210202_P01_WALL-PANEL-ASSY-BACK-LOWER-B2_CAD (Autodesk Fusion 360 design; units mm, degrees)
description: WALL - PANEL ASSY - BACK LOWER - B2 | Vách hậu - cụm tấm dưới phải | P01 | position B2
part number: 210202
description: WALL - PANEL FRAME - BACK LOWER - B2 | Vách hậu - khung dưới phải | P01
part number: 211202
description: WALL - SKIN - BACK LOWER - B2 | Vách hậu - tấm ốp alu dưới phải | P01
part number: 211402
description: WALL - CAVITY FILL - BACK LOWER - B2 | Vách hậu - bông PET dưới phải | P01
part number: 211602
description: HARDWARE - STOP WASHER - Ø10.5 X Ø20 X 1.5 - AL | Long đen chặn nhôm | P01
part number: 831002
description: HARDWARE - RIVET NUT - M6 - SHEREX CAH3-610-4.2 | Tán rút M6 | P01
part number: 838003
description: HARDWARE - LOCATING SPIGOT - M6 X Ø8 - STAINLESS | Chốt định vị Ø8 | P01
part number: 831001
Autodesk Fusion 360 part; units mm, degrees
(part 1 of 2)
ref_plane "WorkPlane1" through (0, 0, 112.26) normal (0, 0, 1) x (1, 0, 0) in component "211202 WALL - PANEL FRAME - BACK LOWER - B2"
sketch "SKETCH - RAIL - BOTTOM TUBE" plane through (0, 0, 112.26) normal (0, 0, 1) x (1, 0, 0) in component "211202 WALL - PANEL FRAME - BACK LOWER - B2"
  line L0 (2.75, 804) -> (1201.74, 804)
  line L1 (1201.74, 804) -> (1201.74, 844)
  line L2 (1201.74, 844) -> (2.75, 844)
  line L3 (2.75, 844) -> (2.75, 804)
  dimension "d175" = 1198.99
  dimension "d176" = 40
  dimension "d177" = 2.75
  dimension "d178" = 804
  constraint horizontal L0
  constraint vertical L1
  constraint horizontal L2
  constraint vertical L3
  measures "d175" horizontal distance of L0.start L0.end
  measures "d176" vertical distance of L0.start L2.end
  measures "d177" horizontal distance of origin L0.start
  measures "d178" vertical distance of origin L0.start
extrude "EXTRUDE - RAIL - BOTTOM TUBE" add sketch "SKETCH - RAIL - BOTTOM TUBE" along normal blind 20 makes body 1 in component "211202 WALL - PANEL FRAME - BACK LOWER - B2"
ref_plane "WorkPlane2" through (0, 0, 113.46) normal (0, 0, 1) x (1, 0, 0) in component "211202 WALL - PANEL FRAME - BACK LOWER - B2"
sketch "SKETCH - RAIL - BOTTOM BORE" plane through (0, 0, 113.46) normal (0, 0, 1) x (1, 0, 0) in component "211202 WALL - PANEL FRAME - BACK LOWER - B2"
  line L0 (2.75, 805.2) -> (1201.74, 805.2)
  line L1 (1201.74, 805.2) -> (1201.74, 842.8)
  line L2 (1201.74, 842.8) -> (2.75, 842.8)
  line L3 (2.75, 842.8) -> (2.75, 805.2)
  dimension "d183" = 1198.99
  dimension "d184" = 37.6
  dimension "d185" = 2.75
  dimension "d186" = 805.2
  constraint horizontal L0
  constraint vertical L1
  constraint horizontal L2
  constraint vertical L3
  measures "d183" horizontal distance of L0.start L0.end
  measures "d184" vertical distance of L0.start L2.end
  measures "d185" horizontal distance of origin L0.start
  measures "d186" vertical distance of origin L0.start
extrude "CUT - RAIL - BOTTOM BORE" cut sketch "SKETCH - RAIL - BOTTOM BORE" along normal blind 17.6 bodies 1 in component "211202 WALL - PANEL FRAME - BACK LOWER - B2"
ref_plane "WorkPlane3" through (0, 0, 1210.87) normal (0, 0, 1) x (1, 0, 0) in component "211202 WALL - PANEL FRAME - BACK LOWER - B2"
sketch "SKETCH - RAIL - TOP TUBE" plane through (0, 0, 1210.87) normal (0, 0, 1) x (1, 0, 0) in component "211202 WALL - PANEL FRAME - BACK LOWER - B2"
  line L0 (2.75, 804) -> (1201.74, 804)
  line L1 (1201.74, 804) -> (1201.74, 844)
  line L2 (1201.74, 844) -> (2.75, 844)
  line L3 (2.75, 844) -> (2.75, 804)
  dimension "d191" = 1198.99
  dimension "d192" = 40
  dimension "d193" = 2.75
  dimension "d194" = 804
  constraint horizontal L0
  constraint vertical L1
  constraint horizontal L2
  constraint vertical L3
  measures "d191" horizontal distance of L0.start L0.end
  measures "d192" vertical distance of L0.start L2.end
  measures "d193" horizontal distance of origin L0.start
  measures "d194" vertical distance of origin L0.start
extrude "EXTRUDE - RAIL - TOP TUBE" add sketch "SKETCH - RAIL - TOP TUBE" along normal blind 20 separate body makes body 2 in component "211202 WALL - PANEL FRAME - BACK LOWER - B2"
ref_plane "WorkPlane4" through (0, 0, 1212.07) normal (0, 0, 1) x (1, 0, 0) in component "211202 WALL - PANEL FRAME - BACK LOWER - B2"
sketch "SKETCH - RAIL - TOP BORE" plane through (0, 0, 1212.07) normal (0, 0, 1) x (1, 0, 0) in component "211202 WALL - PANEL FRAME - BACK LOWER - B2"
  line L0 (2.75, 805.2) -> (1201.74, 805.2)
  line L1 (1201.74, 805.2) -> (1201.74, 842.8)
  line L2 (1201.74, 842.8) -> (2.75, 842.8)
  line L3 (2.75, 842.8) -> (2.75, 805.2)
  dimension "d199" = 1198.99
  dimension "d200" = 37.6
  dimension "d201" = 2.75
  dimension "d202" = 805.2
  constraint horizontal L0
  constraint vertical L1
  constraint horizontal L2
  constraint vertical L3
  measures "d199" horizontal distance of L0.start L0.end
  measures "d200" vertical distance of L0.start L2.end
  measures "d201" horizontal distance of origin L0.start
  measures "d202" vertical distance of origin L0.start
extrude "CUT - RAIL - TOP BORE" cut sketch "SKETCH - RAIL - TOP BORE" along normal blind 17.6 bodies 2 in component "211202 WALL - PANEL FRAME - BACK LOWER - B2"
ref_plane "WorkPlane5" through (0, 0, 132.26) normal (0, 0, 1) x (1, 0, 0) in component "211202 WALL - PANEL FRAME - BACK LOWER - B2"
sketch "SKETCH - STILE - CENTRE TUBE" plane through (0, 0, 132.26) normal (0, 0, 1) x (1, 0, 0) in component "211202 WALL - PANEL FRAME - BACK LOWER - B2"
  line L0 (2.75, 804) -> (22.75, 804)
  line L1 (22.75, 804) -> (22.75, 844)
  line L2 (22.75, 844) -> (2.75, 844)
  line L3 (2.75, 844) -> (2.75, 804)
  dimension "d207" = 20
  dimension "d208" = 40
  dimension "d209" = 2.75
  dimension "d210" = 804
  constraint horizontal L0
  constraint vertical L1
  constraint horizontal L2
  constraint vertical L3
  measures "d207" horizontal distance of L0.start L0.end
  measures "d208" vertical distance of L0.start L2.end
  measures "d209" horizontal distance of origin L0.start
  measures "d210" vertical distance of origin L0.start
extrude "EXTRUDE - STILE - CENTRE TUBE" add sketch "SKETCH - STILE - CENTRE TUBE" along normal blind 1078.61 separate body makes body 3 in component "211202 WALL - PANEL FRAME - BACK LOWER - B2"
ref_plane "WorkPlane6" through (0, 0, 132.26) normal (0, 0, 1) x (1, 0, 0) in component "211202 WALL - PANEL FRAME - BACK LOWER - B2"
sketch "SKETCH - STILE - CENTRE BORE" plane through (0, 0, 132.26) normal (0, 0, 1) x (1, 0, 0) in component "211202 WALL - PANEL FRAME - BACK LOWER - B2"
  line L0 (3.95, 805.2) -> (21.55, 805.2)
  line L1 (21.55, 805.2) -> (21.55, 842.8)
  line L2 (21.55, 842.8) -> (3.95, 842.8)
  line L3 (3.95, 842.8) -> (3.95, 805.2)
  dimension "d215" = 17.6
  dimension "d216" = 37.6
  dimension "d217" = 3.95
  dimension "d218" = 805.2
  constraint horizontal L0
  constraint vertical L1
  constraint horizontal L2
  constraint vertical L3
  measures "d215" horizontal distance of L0.start L0.end
  measures "d216" vertical distance of L0.start L2.end
  measures "d217" horizontal distance of origin L0.start
  measures "d218" vertical distance of origin L0.start
extrude "CUT - STILE - CENTRE BORE" cut sketch "SKETCH - STILE - CENTRE BORE" along normal blind 1078.61 bodies 3 in component "211202 WALL - PANEL FRAME - BACK LOWER - B2"
ref_plane "WorkPlane7" through (0, 0, 132.26) normal (0, 0, 1) x (1, 0, 0) in component "211202 WALL - PANEL FRAME - BACK LOWER - B2"
sketch "SKETCH - STILE - OUTER TUBE" plane through (0, 0, 132.26) normal (0, 0, 1) x (1, 0, 0) in component "211202 WALL - PANEL FRAME - BACK LOWER - B2"
  line L0 (1181.74, 804) -> (1201.74, 804)
  line L1 (1201.74, 804) -> (1201.74, 844)
  line L2 (1201.74, 844) -> (1181.74, 844)
  line L3 (1181.74, 844) -> (1181.74, 804)
  dimension "d223" = 20
  dimension "d224" = 40
  dimension "d225" = 1181.74
  dimension "d226" = 804
  constraint horizontal L0
  constraint vertical L1
  constraint horizontal L2
  constraint vertical L3
  measures "d223" horizontal distance of L0.start L0.end
  measures "d224" vertical distance of L0.start L2.end
  measures "d225" horizontal distance of origin L0.start
  measures "d226" vertical distance of origin L0.start
extrude "EXTRUDE - STILE - OUTER TUBE" add sketch "SKETCH - STILE - OUTER TUBE" along normal blind 1078.61 separate body makes body 4 in component "211202 WALL - PANEL FRAME - BACK LOWER - B2"
ref_plane "WorkPlane8" through (0, 0, 132.26) normal (0, 0, 1) x (1, 0, 0) in component "211202 WALL - PANEL FRAME - BACK LOWER - B2"
sketch "SKETCH - STILE - OUTER BORE" plane through (0, 0, 132.26) normal (0, 0, 1) x (1, 0, 0) in component "211202 WALL - PANEL FRAME - BACK LOWER - B2"
  line L0 (1182.94, 805.2) -> (1200.54, 805.2)
  line L1 (1200.54, 805.2) -> (1200.54, 842.8)
  line L2 (1200.54, 842.8) -> (1182.94, 842.8)
  line L3 (1182.94, 842.8) -> (1182.94, 805.2)
  dimension "d231" = 17.6
  dimension "d232" = 37.6
  dimension "d233" = 1182.94
  dimension "d234" = 805.2
  constraint horizontal L0
  constraint vertical L1
  constraint horizontal L2
  constraint vertical L3
  measures "d231" horizontal distance of L0.start L0.end
  measures "d232" vertical distance of L0.start L2.end
  measures "d233" horizontal distance of origin L0.start
  measures "d234" vertical distance of origin L0.start
extrude "CUT - STILE - OUTER BORE" cut sketch "SKETCH - STILE - OUTER BORE" along normal blind 1078.61 bodies 4 in component "211202 WALL - PANEL FRAME - BACK LOWER - B2"
ref_plane "WorkPlane9" through (0, 0, 132.26) normal (0, 0, 1) x (1, 0, 0) in component "211202 WALL - PANEL FRAME - BACK LOWER - B2"
sketch "SKETCH - STILE - MID 1 TUBE" plane through (0, 0, 132.26) normal (0, 0, 1) x (1, 0, 0) in component "211202 WALL - PANEL FRAME - BACK LOWER - B2"
  line L0 (395.7467, 804) -> (415.7467, 804)
  line L1 (415.7467, 804) -> (415.7467, 844)
  line L2 (415.7467, 844) -> (395.7467, 844)
  line L3 (395.7467, 844) -> (395.7467, 804)
  dimension "d239" = 20
  dimension "d240" = 40
  dimension "d241" = 395.7467
  dimension "d242" = 804
  constraint horizontal L0
  constraint vertical L1
  constraint horizontal L2
  constraint vertical L3
  measures "d239" horizontal distance of L0.start L0.end
  measures "d240" vertical distance of L0.start L2.end
  measures "d241" horizontal distance of origin L0.start
  measures "d242" vertical distance of origin L0.start
extrude "EXTRUDE - STILE - MID 1 TUBE" add sketch "SKETCH - STILE - MID 1 TUBE" along normal blind 1078.61 separate body makes body 5 in component "211202 WALL - PANEL FRAME - BACK LOWER - B2"
ref_plane "WorkPlane10" through (0, 0, 132.26) normal (0, 0, 1) x (1, 0, 0) in component "211202 WALL - PANEL FRAME - BACK LOWER - B2"
sketch "SKETCH - STILE - MID 1 BORE" plane through (0, 0, 132.26) normal (0, 0, 1) x (1, 0, 0) in component "211202 WALL - PANEL FRAME - BACK LOWER - B2"
  line L0 (396.7467, 805) -> (414.7467, 805)
  line L1 (414.7467, 805) -> (414.7467, 843)
  line L2 (414.7467, 843) -> (396.7467, 843)
  line L3 (396.7467, 843) -> (396.7467, 805)
  dimension "d247" = 18
  dimension "d248" = 38
  dimension "d249" = 396.7467
  dimension "d250" = 805
  constraint horizontal L0
  constraint vertical L1
  constraint horizontal L2
  constraint vertical L3
  measures "d247" horizontal distance of L0.start L0.end
  measures "d248" vertical distance of L0.start L2.end
  measures "d249" horizontal distance of origin L0.start
  measures "d250" vertical distance of origin L0.start
extrude "CUT - STILE - MID 1 BORE" cut sketch "SKETCH - STILE - MID 1 BORE" along normal blind 1078.61 bodies 5 in component "211202 WALL - PANEL FRAME - BACK LOWER - B2"
pattern_linear "PATTERN - STILES - MID" count 2 spacing 392.9967 along (1, 0, 0) of bodies 5 makes body 6 in component "211202 WALL - PANEL FRAME - BACK LOWER - B2"
ref_plane "WorkPlane1" through (0, 0, 112.26) normal (0, 0, 1) x (1, 0, 0) in component "211402 WALL - SKIN - BACK LOWER - B2"
sketch "SKETCH - SKIN PLATE" plane through (0, 0, 112.26) normal (0, 0, 1) x (1, 0, 0) in component "211402 WALL - SKIN - BACK LOWER - B2"
  line L0 (1.13, 847) -> (1201.74, 847)
  line L1 (1201.74, 847) -> (1201.74, 850)
  line L2 (1201.74, 850) -> (1.13, 850)
  line L3 (1.13, 850) -> (1.13, 847)
  dimension "d259" = 1200.61
  dimension "d260" = 3
  dimension "d261" = 1.13
  dimension "d262" = 847
  constraint horizontal L0
  constraint vertical L1
  constraint horizontal L2
  constraint vertical L3
  measures "d259" horizontal distance of L0.start L0.end
  measures "d260" vertical distance of L0.start L2.end
  measures "d261" horizontal distance of origin L0.start
  measures "d262" vertical distance of origin L0.start
extrude "EXTRUDE - SKIN PLATE" add sketch "SKETCH - SKIN PLATE" along normal blind 1118.61 separate body makes body 7 in component "211402 WALL - SKIN - BACK LOWER - B2"
ref_plane "WorkPlane2" through (0, 850, 0) normal (0, 1, 0) x (0, 0, 1) in component "211402 WALL - SKIN - BACK LOWER - B2"
sketch "HOLE CENTRE - SKIN MAINS INLET" plane through (0, 850, 0) normal (0, 1, 0) x (1, 0, 0) in component "211402 WALL - SKIN - BACK LOWER - B2"
  point P0 (120, -313)
  dimension "d267" = 120
  dimension "d268" = 313
  measures "d267" horizontal distance of origin P0
  measures "d268" vertical distance of origin P0
hole "HOLE - SKIN MAINS INLET" at (120, 850, 313) direction (0, -1, 0) diameter 24 depth 4 tip angle 118 bodies 7 in component "211402 WALL - SKIN - BACK LOWER - B2"
ref_plane "WorkPlane3" through (0, 850, 0) normal (0, 1, 0) x (0, 0, 1) in component "211402 WALL - SKIN - BACK LOWER - B2"
sketch "HOLE CENTRE - SKIN LAN FEED-THROUGH" plane through (0, 850, 0) normal (0, 1, 0) x (1, 0, 0) in component "211402 WALL - SKIN - BACK LOWER - B2"
  point P0 (120, -375)
  dimension "d274" = 120
  dimension "d275" = 375
  measures "d274" horizontal distance of origin P0
  measures "d275" vertical distance of origin P0
hole "HOLE - SKIN LAN FEED-THROUGH" at (120, 850, 375) direction (0, -1, 0) diameter 24 depth 4 tip angle 118 bodies 7 in component "211402 WALL - SKIN - BACK LOWER - B2"
ref_plane "WorkPlane1" through (0, 0, 132.26) normal (0, 0, 1) x (1, 0, 0) in component "211602 WALL - CAVITY FILL - BACK LOWER - B2"
sketch "SKETCH - FILL BAY 1" plane through (0, 0, 132.26) normal (0, 0, 1) x (1, 0, 0) in component "211602 WALL - CAVITY FILL - BACK LOWER - B2"
  line L0 (22.75, 804) -> (395.7467, 804)
  line L1 (395.7467, 804) -> (395.7467, 844)
  line L2 (395.7467, 844) -> (22.75, 844)
  line L3 (22.75, 844) -> (22.75, 804)
  dimension "d281" = 372.9967
  dimension "d282" = 40
  dimension "d283" = 22.75
  dimension "d284" = 804
  constraint horizontal L0
  constraint vertical L1
  constraint horizontal L2
  constraint vertical L3
  measures "d281" horizontal distance of L0.start L0.end
  measures "d282" vertical distance of L0.start L2.end
  measures "d283" horizontal distance of origin L0.start
  measures "d284" vertical distance of origin L0.start
extrude "EXTRUDE - FILL BAY 1" add sketch "SKETCH - FILL BAY 1" along normal blind 1078.61 separate body makes body 8 in component "211602 WALL - CAVITY FILL - BACK LOWER - B2"
pattern_linear "PATTERN - FILL BAYS" count 3 spacing 392.9967 along (1, 0, 0) of bodies 8 makes body 9 at (664.4111, 844, 851.3333) makes body 10 at (1057.4078, 844, 851.3333) in component "211602 WALL - CAVITY FILL - BACK LOWER - B2"
ref_plane "WorkPlane2" through (0, 0, 132.26) normal (0, 0, 1) x (1, 0, 0) in component "211602 WALL - CAVITY FILL - BACK LOWER - B2"
sketch "SKETCH - FILL POCKET BOTTOM BOLT 1" plane through (0, 0, 132.26) normal (0, 0, 1) x (1, 0, 0) in component "211602 WALL - CAVITY FILL - BACK LOWER - B2"
  line L0 (192.75, 804) -> (252.75, 804)
  line L1 (252.75, 804) -> (252.75, 844)
  line L2 (252.75, 844) -> (192.75, 844)
  line L3 (192.75, 844) -> (192.75, 804)
  dimension "d293" = 60
  dimension "d294" = 40
  dimension "d295" = 192.75
  dimension "d296" = 804
  constraint horizontal L0
  constraint vertical L1
  constraint horizontal L2
  constraint vertical L3
  measures "d293" horizontal distance of L0.start L0.end
  measures "d294" vertical distance of L0.start L2.end
  measures "d295" horizontal distance of origin L0.start
  measures "d296" vertical distance of origin L0.start
extrude "CUT - FILL POCKET BOTTOM BOLT 1" cut sketch "SKETCH - FILL POCKET BOTTOM BOLT 1" along normal blind 60 bodies 8 in component "211602 WALL - CAVITY FILL - BACK LOWER - B2"
ref_plane "WorkPlane3" through (0, 0, 132.26) normal (0, 0, 1) x (1, 0, 0) in component "211602 WALL - CAVITY FILL - BACK LOWER - B2"
sketch "SKETCH - FILL POCKET BOTTOM BOLT 2" plane through (0, 0, 132.26) normal (0, 0, 1) x (1, 0, 0) in component "211602 WALL - CAVITY FILL - BACK LOWER - B2"
  line L0 (445.7467, 804) -> (505.7467, 804)
  line L1 (505.7467, 804) -> (505.7467, 844)
  line L2 (505.7467, 844) -> (445.7467, 844)
  line L3 (445.7467, 844) -> (445.7467, 804)
  dimension "d301" = 60
  dimension "d302" = 40
  dimension "d303" = 445.7467
  dimension "d304" = 804
  constraint horizontal L0
  constraint vertical L1
  constraint horizontal L2
  constraint vertical L3
  measures "d301" horizontal distance of L0.start L0.end
  measures "d302" vertical distance of L0.start L2.end
  measures "d303" horizontal distance of origin L0.start
  measures "d304" vertical distance of origin L0.start
extrude "CUT - FILL POCKET BOTTOM BOLT 2" cut sketch "SKETCH - FILL POCKET BOTTOM BOLT 2" along normal blind 60 bodies 9 in component "211602 WALL - CAVITY FILL - BACK LOWER - B2"
ref_plane "WorkPlane4" through (0, 0, 132.26) normal (0, 0, 1) x (1, 0, 0) in component "211602 WALL - CAVITY FILL - BACK LOWER - B2"
sketch "SKETCH - FILL POCKET BOTTOM BOLT 3" plane through (0, 0, 132.26) normal (0, 0, 1) x (1, 0, 0) in component "211602 WALL - CAVITY FILL - BACK LOWER - B2"
  line L0 (698.7433, 804) -> (758.7433, 804)
  line L1 (758.7433, 804) -> (758.7433, 844)
  line L2 (758.7433, 844) -> (698.7433, 844)
  line L3 (698.7433, 844) -> (698.7433, 804)
  dimension "d309" = 60
  dimension "d310" = 40
  dimension "d311" = 698.7433
  dimension "d312" = 804
  constraint horizontal L0
  constraint vertical L1
  constraint horizontal L2
  constraint vertical L3
  measures "d309" horizontal distance of L0.start L0.end
  measures "d310" vertical distance of L0.start L2.end
  measures "d311" horizontal distance of origin L0.start
  measures "d312" vertical distance of origin L0.start
extrude "CUT - FILL POCKET BOTTOM BOLT 3" cut sketch "SKETCH - FILL POCKET BOTTOM BOLT 3" along normal blind 60 bodies 9 in component "211602 WALL - CAVITY FILL - BACK LOWER - B2"
ref_plane "WorkPlane5" through (0, 0, 132.26) normal (0, 0, 1) x (1, 0, 0) in component "211602 WALL - CAVITY FILL - BACK LOWER - B2"
sketch "SKETCH - FILL POCKET BOTTOM BOLT 4" plane through (0, 0, 132.26) normal (0, 0, 1) x (1, 0, 0) in component "211602 WALL - CAVITY FILL - BACK LOWER - B2"
  line L0 (951.74, 804) -> (1011.74, 804)
  line L1 (1011.74, 804) -> (1011.74, 844)
  line L2 (1011.74, 844) -> (951.74, 844)
  line L3 (951.74, 844) -> (951.74, 804)
  dimension "d317" = 60
  dimension "d318" = 40
  dimension "d319" = 951.74
  dimension "d320" = 804
  constraint horizontal L0
  constraint vertical L1
  constraint horizontal L2
  constraint vertical L3
  measures "d317" horizontal distance of L0.start L0.end
  measures "d318" vertical distance of L0.start L2.end
  measures "d319" horizontal distance of origin L0.start
  measures "d320" vertical distance of origin L0.start
extrude "CUT - FILL POCKET BOTTOM BOLT 4" cut sketch "SKETCH - FILL POCKET BOTTOM BOLT 4" along normal blind 60 bodies 10 in component "211602 WALL - CAVITY FILL - BACK LOWER - B2"
ref_plane "WorkPlane6" through (0, 0, 302.26) normal (0, 0, 1) x (1, 0, 0) in component "211602 WALL - CAVITY FILL - BACK LOWER - B2"
sketch "SKETCH - FILL POCKET CORNER BOLT 1" plane through (0, 0, 302.26) normal (0, 0, 1) x (1, 0, 0) in component "211602 WALL - CAVITY FILL - BACK LOWER - B2"
  line L0 (1121.74, 804) -> (1181.74, 804)
  line L1 (1181.74, 804) -> (1181.74, 844)
  line L2 (1181.74, 844) -> (1121.74, 844)
  line L3 (1121.74, 844) -> (1121.74, 804)
  dimension "d325" = 60
  dimension "d326" = 40
  dimension "d327" = 1121.74
  dimension "d328" = 804
  constraint horizontal L0
  constraint vertical L1
  constraint horizontal L2
  constraint vertical L3
  measures "d325" horizontal distance of L0.start L0.end
  measures "d326" vertical distance of L0.start L2.end
  measures "d327" horizontal distance of origin L0.start
  measures "d328" vertical distance of origin L0.start
extrude "CUT - FILL POCKET CORNER BOLT 1" cut sketch "SKETCH - FILL POCKET CORNER BOLT 1" along normal blind 60 bodies 10 in component "211602 WALL - CAVITY FILL - BACK LOWER - B2"
ref_plane "WorkPlane7" through (0, 0, 641.565) normal (0, 0, 1) x (1, 0, 0) in component "211602 WALL - CAVITY FILL - BACK LOWER - B2"
sketch "SKETCH - FILL POCKET CORNER BOLT 2" plane through (0, 0, 641.565) normal (0, 0, 1) x (1, 0, 0) in component "211602 WALL - CAVITY FILL - BACK LOWER - B2"
  line L0 (1121.74, 804) -> (1181.74, 804)
  line L1 (1181.74, 804) -> (1181.74, 844)
  line L2 (1181.74, 844) -> (1121.74, 844)
  line L3 (1121.74, 844) -> (1121.74, 804)
  dimension "d333" = 60
  dimension "d334" = 40
  dimension "d335" = 1121.74
  dimension "d336" = 804
  constraint horizontal L0
  constraint vertical L1
  constraint horizontal L2
  constraint vertical L3
  measures "d333" horizontal distance of L0.start L0.end
  measures "d334" vertical distance of L0.start L2.end
  measures "d335" horizontal distance of origin L0.start
  measures "d336" vertical distance of origin L0.start
extrude "CUT - FILL POCKET CORNER BOLT 2" cut sketch "SKETCH - FILL POCKET CORNER BOLT 2" along normal blind 60 bodies 10 in component "211602 WALL - CAVITY FILL - BACK LOWER - B2"
ref_plane "WorkPlane8" through (0, 0, 980.87) normal (0, 0, 1) x (1, 0, 0) in component "211602 WALL - CAVITY FILL - BACK LOWER - B2"
sketch "SKETCH - FILL POCKET CORNER BOLT 3" plane through (0, 0, 980.87) normal (0, 0, 1) x (1, 0, 0) in component "211602 WALL - CAVITY FILL - BACK LOWER - B2"
  line L0 (1121.74, 804) -> (1181.74, 804)
  line L1 (1181.74, 804) -> (1181.74, 844)
  line L2 (1181.74, 844) -> (1121.74, 844)
  line L3 (1121.74, 844) -> (1121.74, 804)
  dimension "d341" = 60
  dimension "d342" = 40
  dimension "d343" = 1121.74
  dimension "d344" = 804
  constraint horizontal L0
  constraint vertical L1
  constraint horizontal L2
  constraint vertical L3
  measures "d341" horizontal distance of L0.start L0.end
  measures "d342" vertical distance of L0.start L2.end
  measures "d343" horizontal distance of origin L0.start
  measures "d344" vertical distance of origin L0.start
extrude "CUT - FILL POCKET CORNER BOLT 3" cut sketch "SKETCH - FILL POCKET CORNER BOLT 3" along normal blind 60 bodies 10 in component "211602 WALL - CAVITY FILL - BACK LOWER - B2"
ref_plane "WorkPlane9" through (0, 0, 302.26) normal (0, 0, 1) x (1, 0, 0) in component "211602 WALL - CAVITY FILL - BACK LOWER - B2"
sketch "SKETCH - FILL POCKET CLOSING SEAM BOLT 1" plane through (0, 0, 302.26) normal (0, 0, 1) x (1, 0, 0) in component "211602 WALL - CAVITY FILL - BACK LOWER - B2"
  line L0 (22.75, 804) -> (82.75, 804)
  line L1 (82.75, 804) -> (82.75, 844)
  line L2 (82.75, 844) -> (22.75, 844)
  line L3 (22.75, 844) -> (22.75, 804)
  dimension "d349" = 60
  dimension "d350" = 40
  dimension "d351" = 22.75
  dimension "d352" = 804
  constraint horizontal L0
  constraint vertical L1
  constraint horizontal L2
  constraint vertical L3
  measures "d349" horizontal distance of L0.start L0.end
  measures "d350" vertical distance of L0.start L2.end
  measures "d351" horizontal distance of origin L0.start
  measures "d352" vertical distance of origin L0.start
extrude "CUT - FILL POCKET CLOSING SEAM BOLT 1" cut sketch "SKETCH - FILL POCKET CLOSING SEAM BOLT 1" along normal blind 60 bodies 8 in component "211602 WALL - CAVITY FILL - BACK LOWER - B2"
ref_plane "WorkPlane10" through (0, 0, 641.565) normal (0, 0, 1) x (1, 0, 0) in component "211602 WALL - CAVITY FILL - BACK LOWER - B2"
sketch "SKETCH - FILL POCKET CLOSING SEAM BOLT 2" plane through (0, 0, 641.565) normal (0, 0, 1) x (1, 0, 0) in component "211602 WALL - CAVITY FILL - BACK LOWER - B2"
  line L0 (22.75, 804) -> (82.75, 804)
  line L1 (82.75, 804) -> (82.75, 844)
  line L2 (82.75, 844) -> (22.75, 844)
  line L3 (22.75, 844) -> (22.75, 804)
  dimension "d357" = 60
  dimension "d358" = 40
  dimension "d359" = 22.75
  dimension "d360" = 804
  constraint horizontal L0
  constraint vertical L1
  constraint horizontal L2
  constraint vertical L3
  measures "d357" horizontal distance of L0.start L0.end
  measures "d358" vertical distance of L0.start L2.end
  measures "d359" horizontal distance of origin L0.start
  measures "d360" vertical distance of origin L0.start
extrude "CUT - FILL POCKET CLOSING SEAM BOLT 2" cut sketch "SKETCH - FILL POCKET CLOSING SEAM BOLT 2" along normal blind 60 bodies 8 in component "211602 WALL - CAVITY FILL - BACK LOWER - B2"
ref_plane "WorkPlane11" through (0, 0, 980.87) normal (0, 0, 1) x (1, 0, 0) in component "211602 WALL - CAVITY FILL - BACK LOWER - B2"
sketch "SKETCH - FILL POCKET CLOSING SEAM BOLT 3" plane through (0, 0, 980.87) normal (0, 0, 1) x (1, 0, 0) in component "211602 WALL - CAVITY FILL - BACK LOWER - B2"
  line L0 (22.75, 804) -> (82.75, 804)
  line L1 (82.75, 804) -> (82.75, 844)
  line L2 (82.75, 844) -> (22.75, 844)
  line L3 (22.75, 844) -> (22.75, 804)
  dimension "d365" = 60
  dimension "d366" = 40
  dimension "d367" = 22.75
  dimension "d368" = 804
  constraint horizontal L0
  constraint vertical L1
  constraint horizontal L2
  constraint vertical L3
  measures "d365" horizontal distance of L0.start L0.end
  measures "d366" vertical distance of L0.start L2.end
  measures "d367" horizontal distance of origin L0.start
  measures "d368" vertical distance of origin L0.start
extrude "CUT - FILL POCKET CLOSING SEAM BOLT 3" cut sketch "SKETCH - FILL POCKET CLOSING SEAM BOLT 3" along normal blind 60 bodies 8 in component "211602 WALL - CAVITY FILL - BACK LOWER - B2"
ref_plane "WorkPlane12" through (0, 0, 866) normal (0, 0, 1) x (1, 0, 0) in component "211602 WALL - CAVITY FILL - BACK LOWER - B2"
sketch "SKETCH - FILL CUT-OUT POWER UNIT" plane through (0, 0, 866) normal (0, 0, 1) x (1, 0, 0) in component "211602 WALL - CAVITY FILL - BACK LOWER - B2"
  line L0 (91, 803) -> (405.7467, 803)
  line L1 (405.7467, 803) -> (405.7467, 845)
  line L2 (405.7467, 845) -> (91, 845)
  line L3 (91, 845) -> (91, 803)
  dimension "d373" = 314.7467
  dimension "d374" = 42
  dimension "d375" = 91
  dimension "d376" = 803
  constraint horizontal L0
  constraint vertical L1
  constraint horizontal L2
  constraint vertical L3
  measures "d373" horizontal distance of L0.start L0.end
  measures "d374" vertical distance of L0.start L2.end
  measures "d375" horizontal distance of origin L0.start
  measures "d376" vertical distance of origin L0.start
extrude "CUT - FILL CUT-OUT POWER UNIT" cut sketch "SKETCH - FILL CUT-OUT POWER UNIT" along normal blind 268 bodies 8 in component "211602 WALL - CAVITY FILL - BACK LOWER - B2"
ref_plane "WorkPlane13" through (0, 0, 301) normal (0, 0, 1) x (1, 0, 0) in component "211602 WALL - CAVITY FILL - BACK LOWER - B2"
sketch "SKETCH - FILL CUT-OUT SLEEVE" plane through (0, 0, 301) normal (0, 0, 1) x (1, 0, 0) in component "211602 WALL - CAVITY FILL - BACK LOWER - B2"
  line L0 (140, 803) -> (160, 803)
  line L1 (160, 803) -> (160, 845)
  line L2 (160, 845) -> (140, 845)
  line L3 (140, 845) -> (140, 803)
  dimension "d381" = 20
  dimension "d382" = 42
  dimension "d383" = 140
  dimension "d384" = 803
  constraint horizontal L0
  constraint vertical L1
  constraint horizontal L2
  constraint vertical L3
  measures "d381" horizontal distance of L0.start L0.end
  measures "d382" vertical distance of L0.start L2.end
  measures "d383" horizontal distance of origin L0.start
  measures "d384" vertical distance of origin L0.start
extrude "CUT - FILL CUT-OUT SLEEVE" cut sketch "SKETCH - FILL CUT-OUT SLEEVE" along normal blind 565 bodies 8 in component "211602 WALL - CAVITY FILL - BACK LOWER - B2"
ref_plane "WorkPlane14" through (0, 0, 301) normal (0, 0, 1) x (1, 0, 0) in component "211602 WALL - CAVITY FILL - BACK LOWER - B2"
sketch "SKETCH - FILL CUT-OUT INLET AND LAN" plane through (0, 0, 301) normal (0, 0, 1) x (1, 0, 0) in component "211602 WALL - CAVITY FILL - BACK LOWER - B2"
  line L0 (108, 803) -> (160, 803)
  line L1 (160, 803) -> (160, 845)
  line L2 (160, 845) -> (108, 845)
  line L3 (108, 845) -> (108, 803)
  dimension "d389" = 52
  dimension "d390" = 42
  dimension "d391" = 108
  dimension "d392" = 803
  constraint horizontal L0
  constraint vertical L1
  constraint horizontal L2
  constraint vertical L3
  measures "d389" horizontal distance of L0.start L0.end
  measures "d390" vertical distance of L0.start L2.end
  measures "d391" horizontal distance of origin L0.start
  measures "d392" vertical distance of origin L0.start
extrude "CUT - FILL CUT-OUT INLET AND LAN" cut sketch "SKETCH - FILL CUT-OUT INLET AND LAN" along normal blind 86 bodies 8 in component "211602 WALL - CAVITY FILL - BACK LOWER - B2"
ref_plane "WorkPlane11" through (0, 0, 112.26) normal (0, 0, 1) x (1, 0, 0) in component "211202 WALL - PANEL FRAME - BACK LOWER - B2"
sketch "HOLE CENTRE - BOTTOM RAIL BOLT CLEARANCE 1" plane through (0, 0, 112.26) normal (0, 0, 1) x (1, 0, 0) in component "211202 WALL - PANEL FRAME - BACK LOWER - B2"
  point P0 (222.75, 824)
  dimension "d397" = 222.75
  dimension "d398" = 824
  measures "d397" horizontal distance of origin P0
  measures "d398" vertical distance of origin P0
hole "HOLE - BOTTOM RAIL BOLT CLEARANCE 1" at (222.75, 824, 112.26) direction (0, 0, 1) diameter 7 depth 1.2 tip angle 118 bodies 1 in component "211202 WALL - PANEL FRAME - BACK LOWER - B2"
ref_plane "WorkPlane12" through (0, 0, 132.26) normal (0, 0, 1) x (1, 0, 0) in component "211202 WALL - PANEL FRAME - BACK LOWER - B2"
sketch "HOLE CENTRE - BOTTOM RAIL KEY ACCESS 1" plane through (0, 0, 132.26) normal (0, 0, 1) x (1, 0, 0) in component "211202 WALL - PANEL FRAME - BACK LOWER - B2"
  point P0 (222.75, 824)
  dimension "d404" = 222.75
  dimension "d405" = 824
  measures "d404" horizontal distance of origin P0
  measures "d405" vertical distance of origin P0
hole "HOLE - BOTTOM RAIL KEY ACCESS 1" at (222.75, 824, 132.26) direction (0, 0, -1) diameter 19 depth 1.2 tip angle 118 bodies 1 in component "211202 WALL - PANEL FRAME - BACK LOWER - B2"
pattern_linear "PATTERN - BOTTOM RAIL BOLT HOLES" count 4 spacing 252.9967 along (1, 0, 0) of "HOLE - BOTTOM RAIL BOLT CLEARANCE 1", "HOLE - BOTTOM RAIL KEY ACCESS 1" in component "211202 WALL - PANEL FRAME - BACK LOWER - B2"
ref_plane "WorkPlane13" through (0, 0, 112.26) normal (0, 0, 1) x (1, 0, 0) in component "211202 WALL - PANEL FRAME - BACK LOWER - B2"
sketch "HOLE CENTRE - BOTTOM RAIL SPIGOT ROUND" plane through (0, 0, 112.26) normal (0, 0, 1) x (1, 0, 0) in component "211202 WALL - PANEL FRAME - BACK LOWER - B2"
  point P0 (102.75, 824)
  dimension "d415" = 102.75
  dimension "d416" = 824
  measures "d415" horizontal distance of origin P0
  measures "d416" vertical distance of origin P0
hole "HOLE - BOTTOM RAIL SPIGOT ROUND" at (102.75, 824, 112.26) direction (0, 0, 1) diameter 8.5 depth 1.2 tip angle 118 bodies 1 in component "211202 WALL - PANEL FRAME - BACK LOWER - B2"
ref_plane "WorkPlane14" through (0, 0, 112.26) normal (0, 0, 1) x (1, 0, 0) in component "211202 WALL - PANEL FRAME - BACK LOWER - B2"
sketch "SKETCH - BOTTOM RAIL SPIGOT SLOT" plane through (0, 0, 112.26) normal (0, 0, 1) x (1, 0, 0) in component "211202 WALL - PANEL FRAME - BACK LOWER - B2"
  line L0 (1098.99, 819.75) -> (1104.49, 819.75)
  line L1 (1104.49, 819.75) -> (1104.49, 828.25)
  line L2 (1104.49, 828.25) -> (1098.99, 828.25)
  line L3 (1098.99, 828.25) -> (1098.99, 819.75)
  dimension "d422" = 5.5
  dimension "d423" = 8.5
  dimension "d424" = 1098.99
  dimension "d425" = 819.75
  constraint horizontal L0
  constraint vertical L1
  constraint horizontal L2
  constraint vertical L3
  measures "d422" horizontal distance of L0.start L0.end
  measures "d423" vertical distance of L0.start L2.end
  measures "d424" horizontal distance of origin L0.start
  measures "d425" vertical distance of origin L0.start
extrude "CUT - BOTTOM RAIL SPIGOT SLOT" cut sketch "SKETCH - BOTTOM RAIL SPIGOT SLOT" along normal blind 1.2 bodies 1 in component "211202 WALL - PANEL FRAME - BACK LOWER - B2"
ref_plane "WorkPlane15" through (0, 0, 112.26) normal (0, 0, 1) x (1, 0, 0) in component "211202 WALL - PANEL FRAME - BACK LOWER - B2"
sketch "HOLE CENTRE - BOTTOM RAIL SPIGOT SLOT END 1" plane through (0, 0, 112.26) normal (0, 0, 1) x (1, 0, 0) in component "211202 WALL - PANEL FRAME - BACK LOWER - B2"
  point P0 (1098.99, 824)
  dimension "d430" = 1098.99
  dimension "d431" = 824
  measures "d430" horizontal distance of origin P0
  measures "d431" vertical distance of origin P0
hole "HOLE - BOTTOM RAIL SPIGOT SLOT END 1" at (1098.99, 824, 112.26) direction (0, 0, 1) diameter 8.5 depth 1.2 tip angle 118 bodies 1 in component "211202 WALL - PANEL FRAME - BACK LOWER - B2"
ref_plane "WorkPlane16" through (0, 0, 112.26) normal (0, 0, 1) x (1, 0, 0) in component "211202 WALL - PANEL FRAME - BACK LOWER - B2"
sketch "HOLE CENTRE - BOTTOM RAIL SPIGOT SLOT END 2" plane through (0, 0, 112.26) normal (0, 0, 1) x (1, 0, 0) in component "211202 WALL - PANEL FRAME - BACK LOWER - B2"
  point P0 (1104.49, 824)
  dimension "d437" = 1104.49
  dimension "d438" = 824
  measures "d437" horizontal distance of origin P0
  measures "d438" vertical distance of origin P0
hole "HOLE - BOTTOM RAIL SPIGOT SLOT END 2" at (1104.49, 824, 112.26) direction (0, 0, 1) diameter 8.5 depth 1.2 tip angle 118 bodies 1 in component "211202 WALL - PANEL FRAME - BACK LOWER - B2"
ref_plane "WorkPlane17" through (0, 0, 1230.87) normal (0, 0, 1) x (1, 0, 0) in component "211202 WALL - PANEL FRAME - BACK LOWER - B2"
sketch "HOLE CENTRE - TOP RAIL RIVNUT 1" plane through (0, 0, 1230.87) normal (0, 0, 1) x (1, 0, 0) in component "211202 WALL - PANEL FRAME - BACK LOWER - B2"
  point P0 (222.75, 824)
  dimension "d444" = 222.75
  dimension "d445" = 824
  measures "d444" horizontal distance of origin P0
  measures "d445" vertical distance of origin P0
hole "HOLE - TOP RAIL RIVNUT 1" at (222.75, 824, 1230.87) direction (0, 0, -1) diameter 9.53 depth 1.2 tip angle 118 bodies 2 in component "211202 WALL - PANEL FRAME - BACK LOWER - B2"
pattern_linear "PATTERN - TOP RAIL RIVNUTS" count 4 spacing 252.9967 along (1, 0, 0) of "HOLE - TOP RAIL RIVNUT 1" in component "211202 WALL - PANEL FRAME - BACK LOWER - B2"
ref_plane "WorkPlane18" through (0, 0, 1230.87) normal (0, 0, 1) x (1, 0, 0) in component "211202 WALL - PANEL FRAME - BACK LOWER - B2"
sketch "HOLE CENTRE - TOP RAIL SPIGOT RIVNUT LOW X" plane through (0, 0, 1230.87) normal (0, 0, 1) x (1, 0, 0) in component "211202 WALL - PANEL FRAME - BACK LOWER - B2"
  point P0 (102.75, 824)
  dimension "d455" = 102.75
  dimension "d456" = 824
  measures "d455" horizontal distance of origin P0
  measures "d456" vertical distance of origin P0
hole "HOLE - TOP RAIL SPIGOT RIVNUT LOW X" at (102.75, 824, 1230.87) direction (0, 0, -1) diameter 9.53 depth 1.2 tip angle 118 bodies 2 in component "211202 WALL - PANEL FRAME - BACK LOWER - B2"
ref_plane "WorkPlane19" through (0, 0, 1230.87) normal (0, 0, 1) x (1, 0, 0) in component "211202 WALL - PANEL FRAME - BACK LOWER - B2"
sketch "HOLE CENTRE - TOP RAIL SPIGOT RIVNUT HIGH X" plane through (0, 0, 1230.87) normal (0, 0, 1) x (1, 0, 0) in component "211202 WALL - PANEL FRAME - BACK LOWER - B2"
  point P0 (1101.74, 824)
  dimension "d462" = 1101.74
  dimension "d463" = 824
  measures "d462" horizontal distance of origin P0
  measures "d463" vertical distance of origin P0
hole "HOLE - TOP RAIL SPIGOT RIVNUT HIGH X" at (1101.74, 824, 1230.87) direction (0, 0, -1) diameter 9.53 depth 1.2 tip angle 118 bodies 2 in component "211202 WALL - PANEL FRAME - BACK LOWER - B2"
ref_plane "WorkPlane20" through (1201.74, 0, 0) normal (1, 0, 0) x (0, 1, 0) in component "211202 WALL - PANEL FRAME - BACK LOWER - B2"
sketch "HOLE CENTRE - OUTER STILE CORNER BOLT CLEARANCE 1" plane through (1201.74, 0, 0) normal (1, 0, 0) x (0, 0, -1) in component "211202 WALL - PANEL FRAME - BACK LOWER - B2"
  point P0 (-332.26, 824)
  dimension "d469" = 824
  dimension "d470" = 332.26
  measures "d469" vertical distance of origin P0
  measures "d470" horizontal distance of origin P0
hole "HOLE - OUTER STILE CORNER BOLT CLEARANCE 1" at (1201.74, 824, 332.26) direction (-1, 0, 0) diameter 7 depth 1.2 tip angle 118 bodies 4 in component "211202 WALL - PANEL FRAME - BACK LOWER - B2"
ref_plane "WorkPlane21" through (1181.74, 0, 0) normal (1, 0, 0) x (0, 1, 0) in component "211202 WALL - PANEL FRAME - BACK LOWER - B2"
sketch "HOLE CENTRE - OUTER STILE CORNER KEY ACCESS 1" plane through (1181.74, 0, 0) normal (1, 0, 0) x (0, 0, -1) in component "211202 WALL - PANEL FRAME - BACK LOWER - B2"
  point P0 (-332.26, 824)
  dimension "d476" = 824
  dimension "d477" = 332.26
  measures "d476" vertical distance of origin P0
  measures "d477" horizontal distance of origin P0
hole "HOLE - OUTER STILE CORNER KEY ACCESS 1" at (1181.74, 824, 332.26) direction (1, 0, 0) diameter 19 depth 1.2 tip angle 118 bodies 4 in component "211202 WALL - PANEL FRAME - BACK LOWER - B2"
pattern_linear "PATTERN - OUTER STILE CORNER BOLT HOLES" count 3 spacing 339.305 along (0, 0, 1) of "HOLE - OUTER STILE CORNER BOLT CLEARANCE 1", "HOLE - OUTER STILE CORNER KEY ACCESS 1" in component "211202 WALL - PANEL FRAME - BACK LOWER - B2"
ref_plane "WorkPlane22" through (2.75, 0, 0) normal (1, 0, 0) x (0, 1, 0) in component "211202 WALL - PANEL FRAME - BACK LOWER - B2"
sketch "HOLE CENTRE - CENTRE STILE PIN RIVNUT 1" plane through (2.75, 0, 0) normal (1, 0, 0) x (0, 0, -1) in component "211202 WALL - PANEL FRAME - BACK LOWER - B2"
  point P0 (-332.26, 824)
  dimension "d487" = 824
  dimension "d488" = 332.26
  measures "d487" vertical distance of origin P0
  measures "d488" horizontal distance of origin P0
hole "HOLE - CENTRE STILE PIN RIVNUT 1" at (2.75, 824, 332.26) direction (1, 0, 0) diameter 9.53 depth 1.2 tip angle 118 bodies 3 in component "211202 WALL - PANEL FRAME - BACK LOWER - B2"
ref_plane "WorkPlane23" through (22.75, 0, 0) normal (1, 0, 0) x (0, 1, 0) in component "211202 WALL - PANEL FRAME - BACK LOWER - B2"
sketch "HOLE CENTRE - CENTRE STILE PIN KEY ACCESS 1" plane through (22.75, 0, 0) normal (1, 0, 0) x (0, 0, -1) in component "211202 WALL - PANEL FRAME - BACK LOWER - B2"
  point P0 (-332.26, 824)
  dimension "d494" = 824
  dimension "d495" = 332.26
  measures "d494" vertical distance of origin P0
  measures "d495" horizontal distance of origin P0
hole "HOLE - CENTRE STILE PIN KEY ACCESS 1" at (22.75, 824, 332.26) direction (-1, 0, 0) diameter 19 depth 1.2 tip angle 118 bodies 3 in component "211202 WALL - PANEL FRAME - BACK LOWER - B2"
pattern_linear "PATTERN - CENTRE STILE PIN HOLES" count 3 spacing 339.305 along (0, 0, 1) of "HOLE - CENTRE STILE PIN RIVNUT 1", "HOLE - CENTRE STILE PIN KEY ACCESS 1" in component "211202 WALL - PANEL FRAME - BACK LOWER - B2"
chamfer "CHAMFER - CLOSING SEAM LEAD-IN (R-J9)" distance 1 angle 45 1 edges at (2.75, 824, 1230.87) tangent chain off on bodies 2 in component "211202 WALL - PANEL FRAME - BACK LOWER - B2"
ref_plane "WorkPlane1" through (0, 0, 1230.87) normal (0, 0, 1) x (1, 0, 0) in component "831002 HARDWARE - STOP WASHER - Ø10.5 X Ø20 X 1.5 - AL"
sketch "SKETCH - STOP WASHER TOP RAIL" plane through (0, 0, 1230.87) normal (0, 0, 1) x (1, 0, 0) in component "831002 HARDWARE - STOP WASHER - Ø10.5 X Ø20 X 1.5 - AL"
  circle A0 centre (222.75, 824) radius 10
  circle A1 centre (222.75, 824) radius 5.25
  dimension "d506" = 222.75
  dimension "d507" = 824
  dimension "d508" = 20
  dimension "d509" = 10.5
  measures "d506" horizontal distance of origin A0.centre
  measures "d507" vertical distance of origin A0.centre
  measures "d508" diameter of A0
  measures "d509" diameter of A1
extrude "EXTRUDE - STOP WASHER TOP RAIL" add sketch "SKETCH - STOP WASHER TOP RAIL" along normal blind 1.5 separate body makes body 11 in component "831002 HARDWARE - STOP WASHER - Ø10.5 X Ø20 X 1.5 - AL"
ref_plane "WorkPlane1" through (0, 0, 1232.37) normal (0, 0, 1) x (1, 0, 0) in component "838003 HARDWARE - RIVET NUT - M6 - SHEREX CAH3-610-4.2"
sketch "SKETCH - RIVNUT HEAD TOP RAIL" plane through (0, 0, 1232.37) normal (0, 0, 1) x (1, 0, 0) in component "838003 HARDWARE - RIVET NUT - M6 - SHEREX CAH3-610-4.2"
  circle A0 centre (222.75, 824) radius 6.48
  circle A1 centre (222.75, 824) radius 3
  dimension "d514" = 222.75
  dimension "d515" = 824
  dimension "d516" = 12.96
  dimension "d517" = 6
  measures "d514" horizontal distance of origin A0.centre
  measures "d515" vertical distance of origin A0.centre
  measures "d516" diameter of A0
  measures "d517" diameter of A1
extrude "EXTRUDE - RIVNUT HEAD TOP RAIL" add sketch "SKETCH - RIVNUT HEAD TOP RAIL" along normal blind 0.76 separate body makes body 12 in component "838003 HARDWARE - RIVET NUT - M6 - SHEREX CAH3-610-4.2"
ref_plane "WorkPlane2" through (0, 0, 1232.37) normal (0, 0, 1) x (1, 0, 0) in component "838003 HARDWARE - RIVET NUT - M6 - SHEREX CAH3-610-4.2"
sketch "SKETCH - RIVNUT BODY TOP RAIL" plane through (0, 0, 1232.37) normal (0, 0, 1) x (1, 0, 0) in component "838003 HARDWARE - RIVET NUT - M6 - SHEREX CAH3-610-4.2"
  circle A0 centre (222.75, 824) radius 4.75
  circle A1 centre (222.75, 824) radius 3
  dimension "d522" = 222.75
  dimension "d523" = 824
  dimension "d524" = 9.5
  dimension "d525" = 6
  measures "d522" horizontal distance of origin A0.centre
  measures "d523" vertical distance of origin A0.centre
  measures "d524" diameter of A0
  measures "d525" diameter of A1
extrude "EXTRUDE - RIVNUT BODY TOP RAIL" add sketch "SKETCH - RIVNUT BODY TOP RAIL" against normal blind 10.16 separate body makes body 13 in component "838003 HARDWARE - RIVET NUT - M6 - SHEREX CAH3-610-4.2"
combine "COMBINE - RIVNUT TOP RAIL" operation add target body 12 tool bodies 13 in component "838003 HARDWARE - RIVET NUT - M6 - SHEREX CAH3-610-4.2"
pattern_linear "PATTERN - STOP WASHER - TOP RAIL" count 4 spacing 252.9967 along (1, 0, 0) of bodies 11 makes body 14 at (467.5931, 822.0049, 1230.87) makes body 15 at (726.3944, 815.9412, 1230.87) makes body 16 at (979.391, 815.9412, 1230.87) in component "831002 HARDWARE - STOP WASHER - Ø10.5 X Ø20 X 1.5 - AL"
pattern_linear "PATTERN - RIVNUT - TOP RAIL" count 4 spacing 252.9967 along (1, 0, 0) of bodies 12 makes body 17 at (479.3854, 827.0532, 1225.5967) makes body 18 at (729.5682, 828.6778, 1225.5967) makes body 19 at (982.5648, 828.6778, 1225.5967) in component "838003 HARDWARE - RIVET NUT - M6 - SHEREX CAH3-610-4.2"
ref_plane "WorkPlane3" through (0, 0, 1230.87) normal (0, 0, 1) x (1, 0, 0) in component "838003 HARDWARE - RIVET NUT - M6 - SHEREX CAH3-610-4.2"
sketch "SKETCH - RIVNUT HEAD TOP RAIL SPIGOT LOW X" plane through (0, 0, 1230.87) normal (0, 0, 1) x (1, 0, 0) in component "838003 HARDWARE - RIVET NUT - M6 - SHEREX CAH3-610-4.2"
  circle A0 centre (102.75, 824) radius 6.48
  circle A1 centre (102.75, 824) radius 3
  dimension "d540" = 102.75
  dimension "d541" = 824
  dimension "d542" = 12.96
  dimension "d543" = 6
  measures "d540" horizontal distance of origin A0.centre
  measures "d541" vertical distance of origin A0.centre
  measures "d542" diameter of A0
  measures "d543" diameter of A1
extrude "EXTRUDE - RIVNUT HEAD TOP RAIL SPIGOT LOW X" add sketch "SKETCH - RIVNUT HEAD TOP RAIL SPIGOT LOW X" along normal blind 0.76 separate body makes body 20 in component "838003 HARDWARE - RIVET NUT - M6 - SHEREX CAH3-610-4.2"
ref_plane "WorkPlane4" through (0, 0, 1230.87) normal (0, 0, 1) x (1, 0, 0) in component "838003 HARDWARE - RIVET NUT - M6 - SHEREX CAH3-610-4.2"
sketch "SKETCH - RIVNUT BODY TOP RAIL SPIGOT LOW X" plane through (0, 0, 1230.87) normal (0, 0, 1) x (1, 0, 0) in component "838003 HARDWARE - RIVET NUT - M6 - SHEREX CAH3-610-4.2"
  circle A0 centre (102.75, 824) radius 4.75
  circle A1 centre (102.75, 824) radius 3
  dimension "d548" = 102.75
  dimension "d549" = 824
  dimension "d550" = 9.5
  dimension "d551" = 6
  measures "d548" horizontal distance of origin A0.centre
  measures "d549" vertical distance of origin A0.centre
  measures "d550" diameter of A0
  measures "d551" diameter of A1
extrude "EXTRUDE - RIVNUT BODY TOP RAIL SPIGOT LOW X" add sketch "SKETCH - RIVNUT BODY TOP RAIL SPIGOT LOW X" against normal blind 10.16 separate body makes body 21 in component "838003 HARDWARE - RIVET NUT - M6 - SHEREX CAH3-610-4.2"
combine "COMBINE - RIVNUT TOP RAIL SPIGOT LOW X" operation add target body 20 tool bodies 21 in component "838003 HARDWARE - RIVET NUT - M6 - SHEREX CAH3-610-4.2"
ref_plane "WorkPlane1" through (0, 0, 1231.63) normal (0, 0, 1) x (1, 0, 0) in component "831001 HARDWARE - LOCATING SPIGOT - M6 X Ø8 - STAINLESS"
sketch "SKETCH - SPIGOT PIN TOP RAIL SPIGOT LOW X" plane through (0, 0, 1231.63) normal (0, 0, 1) x (1, 0, 0) in component "831001 HARDWARE - LOCATING SPIGOT - M6 X Ø8 - STAINLESS"
  circle A0 centre (102.75, 824) radius 4
  dimension "d558" = 102.75
  dimension "d559" = 824
  dimension "d560" = 8
  measures "d558" horizontal distance of origin A0.centre
  measures "d559" vertical distance of origin A0.centre
  measures "d560" diameter of A0
extrude "EXTRUDE - SPIGOT PIN TOP RAIL SPIGOT LOW X" add sketch "SKETCH - SPIGOT PIN TOP RAIL SPIGOT LOW X" along normal blind 7.24 separate body makes body 22 in component "831001 HARDWARE - LOCATING SPIGOT - M6 X Ø8 - STAINLESS"
ref_plane "WorkPlane2" through (0, 0, 1231.63) normal (0, 0, 1) x (1, 0, 0) in component "831001 HARDWARE - LOCATING SPIGOT - M6 X Ø8 - STAINLESS"
sketch "SKETCH - SPIGOT THREAD TOP RAIL SPIGOT LOW X" plane through (0, 0, 1231.63) normal (0, 0, 1) x (1, 0, 0) in component "831001 HARDWARE - LOCATING SPIGOT - M6 X Ø8 - STAINLESS"
  circle A0 centre (102.75, 824) radius 3
  dimension "d565" = 102.75
  dimension "d566" = 824
  dimension "d567" = 6
  measures "d565" horizontal distance of origin A0.centre
  measures "d566" vertical distance of origin A0.centre
  measures "d567" diameter of A0
extrude "EXTRUDE - SPIGOT THREAD TOP RAIL SPIGOT LOW X" add sketch "SKETCH - SPIGOT THREAD TOP RAIL SPIGOT LOW X" against normal blind 10 separate body makes body 23 in component "831001 HARDWARE - LOCATING SPIGOT - M6 X Ø8 - STAINLESS"
combine "COMBINE - SPIGOT TOP RAIL SPIGOT LOW X" operation add target body 22 tool bodies 23 in component "831001 HARDWARE - LOCATING SPIGOT - M6 X Ø8 - STAINLESS"
ref_plane "WorkPlane5" through (0, 0, 1230.87) normal (0, 0, 1) x (1, 0, 0) in component "838003 HARDWARE - RIVET NUT - M6 - SHEREX CAH3-610-4.2"
sketch "SKETCH - RIVNUT HEAD TOP RAIL SPIGOT HIGH X" plane through (0, 0, 1230.87) normal (0, 0, 1) x (1, 0, 0) in component "838003 HARDWARE - RIVET NUT - M6 - SHEREX CAH3-610-4.2"
  circle A0 centre (1101.74, 824) radius 6.48
  circle A1 centre (1101.74, 824) radius 3
  dimension "d574" = 1101.74
  dimension "d575" = 824
  dimension "d576" = 12.96
  dimension "d577" = 6
  measures "d574" horizontal distance of origin A0.centre
  measures "d575" vertical distance of origin A0.centre
  measures "d576" diameter of A0
  measures "d577" diameter of A1
extrude "EXTRUDE - RIVNUT HEAD TOP RAIL SPIGOT HIGH X" add sketch "SKETCH - RIVNUT HEAD TOP RAIL SPIGOT HIGH X" along normal blind 0.76 separate body makes body 24 in component "838003 HARDWARE - RIVET NUT - M6 - SHEREX CAH3-610-4.2"
ref_plane "WorkPlane6" through (0, 0, 1230.87) normal (0, 0, 1) x (1, 0, 0) in component "838003 HARDWARE - RIVET NUT - M6 - SHEREX CAH3-610-4.2"
sketch "SKETCH - RIVNUT BODY TOP RAIL SPIGOT HIGH X" plane through (0, 0, 1230.87) normal (0, 0, 1) x (1, 0, 0) in component "838003 HARDWARE - RIVET NUT - M6 - SHEREX CAH3-610-4.2"
  circle A0 centre (1101.74, 824) radius 4.75
  circle A1 centre (1101.74, 824) radius 3
  dimension "d582" = 1101.74
  dimension "d583" = 824
  dimension "d584" = 9.5
  dimension "d585" = 6
  measures "d582" horizontal distance of origin A0.centre
  measures "d583" vertical distance of origin A0.centre
  measures "d584" diameter of A0
  measures "d585" diameter of A1
extrude "EXTRUDE - RIVNUT BODY TOP RAIL SPIGOT HIGH X" add sketch "SKETCH - RIVNUT BODY TOP RAIL SPIGOT HIGH X" against normal blind 10.16 separate body makes body 25 in component "838003 HARDWARE - RIVET NUT - M6 - SHEREX CAH3-610-4.2"
combine "COMBINE - RIVNUT TOP RAIL SPIGOT HIGH X" operation add target body 24 tool bodies 25 in component "838003 HARDWARE - RIVET NUT - M6 - SHEREX CAH3-610-4.2"
ref_plane "WorkPlane3" through (0, 0, 1231.63) normal (0, 0, 1) x (1, 0, 0) in component "831001 HARDWARE - LOCATING SPIGOT - M6 X Ø8 - STAINLESS"
sketch "SKETCH - SPIGOT PIN TOP RAIL SPIGOT HIGH X" plane through (0, 0, 1231.63) normal (0, 0, 1) x (1, 0, 0) in component "831001 HARDWARE - LOCATING SPIGOT - M6 X Ø8 - STAINLESS"
  circle A0 centre (1101.74, 824) radius 4
  dimension "d592" = 1101.74
  dimension "d593" = 824
  dimension "d594" = 8
  measures "d592" horizontal distance of origin A0.centre
  measures "d593" vertical distance of origin A0.centre
  measures "d594" diameter of A0
extrude "EXTRUDE - SPIGOT PIN TOP RAIL SPIGOT HIGH X" add sketch "SKETCH - SPIGOT PIN TOP RAIL SPIGOT HIGH X" along normal blind 7.24 separate body makes body 26 in component "831001 HARDWARE - LOCATING SPIGOT - M6 X Ø8 - STAINLESS"